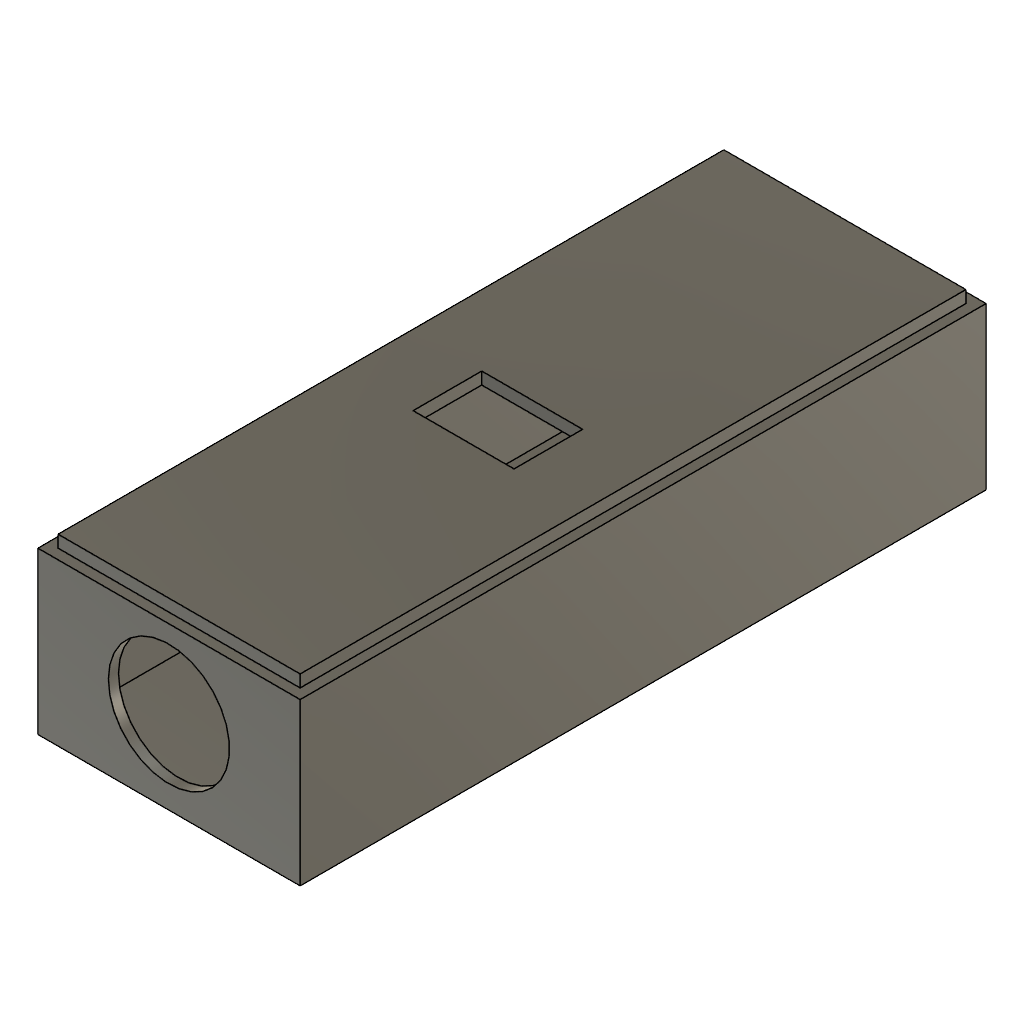
Agua clara Case final (Autodesk Fusion 360 design; units mm, degrees)
part number: 2026-11-20-14-22-47-678
Autodesk Fusion 360 part; units mm, degrees
sketch "Boceto1" plane through (0, 0, 0) normal (0, 0, 1) x (1, 0, 0)
  line L0 (0, 0) -> (65, 0)
  line L1 (65, 0) -> (65, 170)
  line L2 (65, 170) -> (0, 170)
  line L3 (0, 170) -> (0, 0)
  dimension "d1" = 65
  dimension "d2" = 170
  constraint horizontal L0
  constraint vertical L1
  constraint horizontal L2
  constraint vertical L3
  constraint coincident L0.start L3.end
  measures "d1" distance of L0.start L0.end
  measures "d2" distance of L0.start L2.end
extrude "Extruir1" add sketch "Boceto1" along normal blind 40 makes body 1
shell "Vaciado1" thickness 2.5 removed faces 1 at (21.6667, 113.3333, 40) on bodies 1
sketch "Boceto2" plane through (0, 0, 40) normal (0, 0, 1) x (-1, 0, 0)
  line L0 (-2.5, -167.5) -> (-62.5, -167.5)
  line L1 (-62.5, -167.5) -> (-62.5, -2.5)
  line L2 (-62.5, -2.5) -> (-2.5, -2.5)
  line L3 (-2.5, -2.5) -> (-2.5, -167.5)
  line L4 (0, -170) -> (0, 0)
  line L5 (0, 0) -> (-65, 0)
  line L6 (-65, 0) -> (-65, -170)
  line L7 (-65, -170) -> (0, -170)
  line L8 (-62.5, -167.5) -> (-62.5, -2.5)
  line L9 (-2.5, -167.5) -> (-62.5, -167.5)
  line L10 (-2.5, -2.5) -> (-2.5, -167.5)
  line L11 (-62.5, -2.5) -> (-2.5, -2.5)
extrude "Extruir2" add sketch "Boceto2" along normal blind 3 separate body contours L0 L1 L2 L3 L8 L9 L10 L11 makes body 2
sketch "Boceto3" plane through (0, 0, 0) normal (0, -1, 0) x (1, 0, 0)
  line L0 (0, 0) -> (65, 0)
  line L1 (65, 0) -> (65, 40)
  line L2 (65, 40) -> (0, 40)
  line L3 (0, 40) -> (0, 0)
  circle A0 centre (32.493, 20.6523) radius 15
  dimension "d8" = 30
  measures "d8" diameter of A0
extrude "Extruir3" cut sketch "Boceto3" along normal blind 3 and the other way blind 3 contours A0 bodies 1
sketch "Boceto4" plane through (0, 170, 0) normal (0, 1, 0) x (-1, 0, 0)
  line L0 (-65, 0) -> (0, 0)
  line L1 (0, 0) -> (0, 40)
  line L2 (0, 40) -> (-65, 40)
  line L3 (-65, 40) -> (-65, 0)
  line L4 (-60, 0) -> (-40, 0)
  line L5 (-40, 0) -> (-40, 10)
  line L6 (-40, 10) -> (-60, 10)
  line L7 (-60, 10) -> (-60, 0)
  dimension "d13" = 20
  constraint horizontal L4
  constraint vertical L5
  constraint horizontal L6
  constraint vertical L7
  constraint coincident L0 L4.start
  measures "d13" distance of L4.start L4.end
extrude "Extruir4" cut sketch "Boceto4" along normal blind 3 and the other way blind 3 contours L0 L4 L5 L6 L7 bodies 1
sketch "Boceto5" plane through (0, 0, 43) normal (0, 0, 1) x (-1, 0, 0)
  line L0 (-62.5, -2.5) -> (-62.5, -167.5)
  line L1 (-62.5, -167.5) -> (-2.5, -167.5)
  line L2 (-2.5, -167.5) -> (-2.5, -2.5)
  line L3 (-2.5, -2.5) -> (-62.5, -2.5)
  line L4 (-20, -90) -> (-45, -90)
  line L5 (-45, -90) -> (-45, -73)
  line L6 (-45, -73) -> (-20, -73)
  line L7 (-20, -73) -> (-20, -90)
  dimension "d18" = 25
  dimension "d19" = 17
  constraint horizontal L4
  constraint vertical L5
  constraint horizontal L6
  constraint vertical L7
  measures "d18" distance of L4.start L4.end
  measures "d19" distance of L4.start L6.end
extrude "Extruir5" cut sketch "Boceto5" along normal blind 3 and the other way blind 3 contours L4 L5 L6 L7 bodies 2
named bodies: "AguaClara_CajaInferior.V2", "AguaClara_TapaSuperior.V2"
